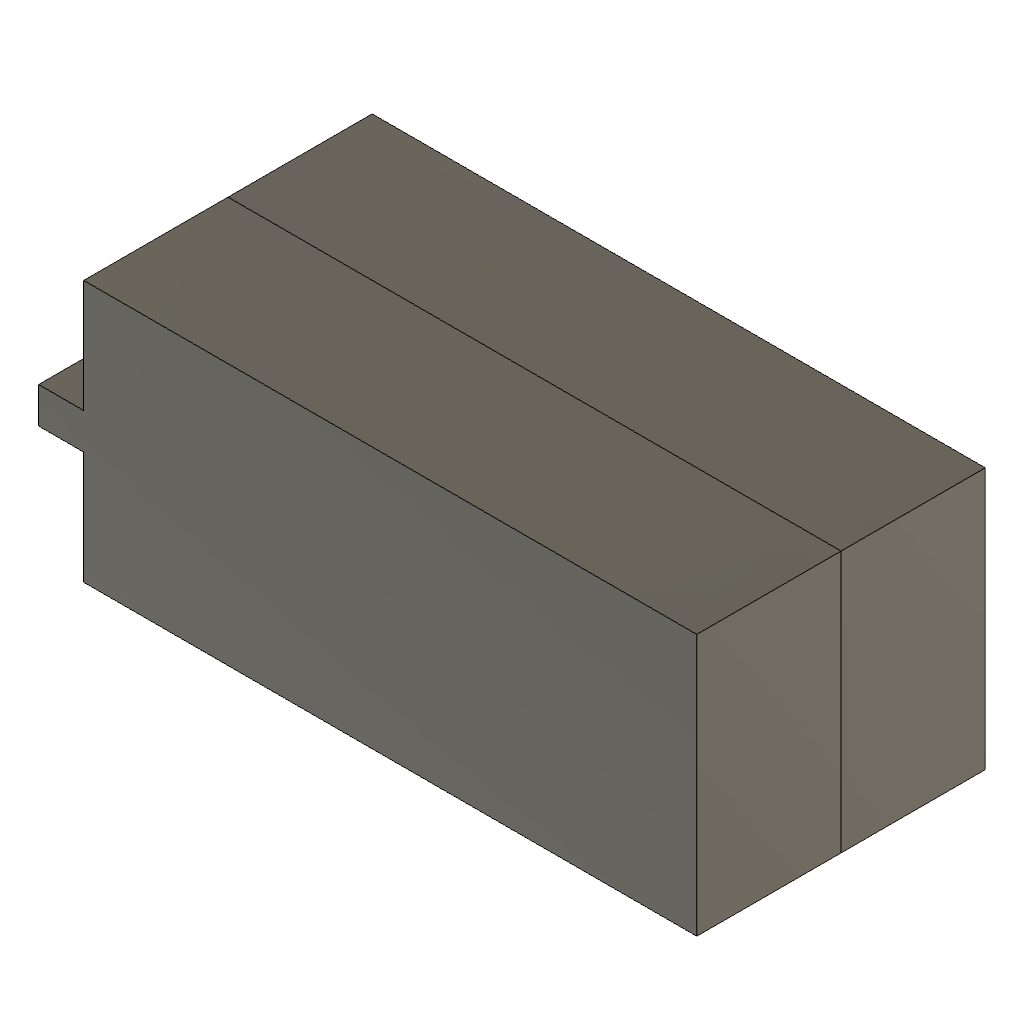
finger_mould_v1 (Autodesk Fusion 360 design; units mm, degrees)
part number: 2026-10-19-20-18-20-436
Autodesk Fusion 360 part; units mm, degrees
sketch "Esquisse2" plane through (0, 0, 0) normal (1, 0, 0) x (0, 1, 0)
  ellipse E0 centre (0, 0) end of major axis (8, 0) minor radius 6.5
  line L0 (-8, 0) -> (8, 0) construction
  line L1 (0, -6.5) -> (0, 6.5) construction
  dimension "d7" = 16
  dimension "d8" = 13
  constraint coincident E0 L0.start
  constraint coincident E0 L0.end
  constraint coincident E0 L1.start
  constraint coincident E0 L1.end
  constraint coincident E0.centre origin
  constraint horizontal L0
  measures "d7" distance of E0
extrude "Extrusion1" add sketch "Esquisse2" along normal blind 60 makes body 1
fillet "Congé1" radius 5 1 faces at (60, -0.0579, -2.16) on bodies 1
sketch "Esquisse3" plane through (0, 0, 0) normal (-1, 0, 0) x (0, -1, 0)
  ellipse E0 centre (0, 0) end of major axis (-8, 0) minor radius 6.5
  circle A0 centre (0, 0) radius 1
  dimension "d15" = 2
  constraint coincident E0.centre A0.centre
  measures "d15" diameter of A0
extrude "Extrusion2" cut sketch "Esquisse3" against normal blind 52 contours A0 bodies 1
sketch "Esquisse4" plane through (0, 0, 0) normal (1, 0, 0) x (0, 1, 0)
  line L0 (16, -14.5) -> (-16, -14.5)
  line L1 (-16, -14.5) -> (-16, 14.5)
  line L2 (-16, 14.5) -> (16, 14.5)
  line L3 (16, 14.5) -> (16, -14.5)
  line L4 (16, -14.5) -> (-16, 14.5) construction
  line L5 (-16, -14.5) -> (16, 14.5) construction
  dimension "d19" = 32
  dimension "d20" = 29
  constraint horizontal L0
  constraint perpendicular L0 L1
  constraint parallel L0 L2
  constraint parallel L1 L3
  constraint coincident L4 origin
  constraint coincident L5 origin
  measures "d19" distance of L1.end L2.end
  measures "d20" distance of L0.end L1.end
extrude "Extrusion3" add sketch "Esquisse4" along normal blind 68 separate body makes body 2
extrude "Extrusion4" add sketch "Esquisse3" along normal blind 15 and the other way blind 52 separate body contours A0 makes body 3
combine "Combiner1" operation cut target body 2 tool bodies 1 3 keep tools
split "Scinder1" by plane through (0, 0, 0) normal (0, 1, 0) bodies 2 makes body 4 at (22.6667, 16, 4.8333)
sketch "Esquisse5" plane through (0, 0, 0) normal (0, 1, 0) x (1, 0, 0)
  circle A0 centre (10, -10.5) radius 1.5
  circle A1 centre (10, 10.5) radius 1.5
  circle A2 centre (50, -10.5) radius 1.5
  circle A3 centre (50, 10.5) radius 1.5
  line L0 (0, 14.5) -> (0, -14.5)
  line L1 (0, -14.5) -> (68, -14.5)
  line L2 (0, 14.5) -> (68, 14.5)
  dimension "d31" = 3
  dimension "d32" = 3
  dimension "d33" = 3
  dimension "d34" = 3
  dimension "d35" = 10
  dimension "d36" = 10
  dimension "d37" = 50
  dimension "d38" = 50
  dimension "d39" = 4
  dimension "d40" = 4
  dimension "d41" = 4
  dimension "d42" = 4
  measures "d31" diameter of A0
  measures "d32" diameter of A1
  measures "d33" diameter of A2
  measures "d34" diameter of A3
  measures "d35" distance of A0.centre L0
  measures "d36" distance of A1.centre L0
  measures "d37" distance of A2.centre L0
  measures "d38" distance of A3.centre L0
  measures "d39" distance of A0.centre L1
  measures "d40" distance of A2.centre L1
  measures "d41" distance of A1.centre L2
  measures "d42" distance of A3.centre L2
extrude "Extrusion5" add sketch "Esquisse5" along normal blind 3 bodies 2
sketch "Esquisse6" plane through (0, 0, 0) normal (0, -1, 0) x (1, 0, 0)
  line L0 (60, 1.5) -> (60, -1.5)
  spline S0 degree 3 poles (55, -6.5) (55.3357, -6.5) (55.6706, -6.4662) (56.3285, -6.3319) (56.6499, -6.2319) (57.5578, -5.8453) (58.1013, -5.4756) (59.016, -4.5489) (59.3785, -4.0006) (59.8728, -2.7959) (60, -2.1511) (60, -1.5) knots -0.787407 -0.787407 -0.787407 -0.787407 -0.686687 -0.686687 -0.585967 -0.585967 -0.390644 -0.390644 -0.195322 -0.195322 0 0 0 0
  line L1 (55, -6.5) -> (0, -6.5)
  line L2 (0, -6.5) -> (0, -14.5)
  line L3 (0, -14.5) -> (68, -14.5)
  line L4 (68, -14.5) -> (68, 14.5)
  line L5 (68, 14.5) -> (0, 14.5)
  line L6 (0, 14.5) -> (0, 6.5)
  line L7 (0, 6.5) -> (55, 6.5)
  spline S1 degree 3 poles (60, 1.5) (60, 1.8357) (59.9662, 2.1706) (59.8319, 2.8285) (59.7319, 3.1499) (59.3453, 4.0578) (58.9756, 4.6013) (58.0489, 5.516) (57.5006, 5.8785) (56.2959, 6.3728) (55.6511, 6.5) (55, 6.5) knots -0.787407 -0.787407 -0.787407 -0.787407 -0.686687 -0.686687 -0.585967 -0.585967 -0.390644 -0.390644 -0.195322 -0.195322 0 0 0 0
  circle A0 centre (10, 10.5) radius 1.7
  circle A1 centre (10, -10.5) radius 1.7
  circle A2 centre (50, 10.5) radius 1.7
  circle A3 centre (50, -10.5) radius 1.7
  dimension "d45" = 3.4
  dimension "d46" = 3.4
  dimension "d47" = 3.4
  dimension "d48" = 3.4
  dimension "d49" = 10
  dimension "d50" = 10
  dimension "d51" = 50
  dimension "d52" = 50
  dimension "d53" = 4
  dimension "d54" = 4
  dimension "d55" = 4
  dimension "d56" = 4
  measures "d45" diameter of A0
  measures "d46" diameter of A2
  measures "d47" diameter of A3
  measures "d48" diameter of A1
  measures "d49" distance of L6 A0.centre
  measures "d50" distance of L2 A1.centre
  measures "d51" distance of L6 A2.centre
  measures "d52" distance of L2 A3.centre
  measures "d53" distance of L5 A0.centre
  measures "d54" distance of L3 A1.centre
  measures "d55" distance of L3 A3.centre
  measures "d56" distance of L5 A2.centre
extrude "Extrusion6" cut sketch "Esquisse6" against normal blind 3.5 contours A0 | A1 | A2 | A3 bodies 4
sketch "Esquisse7" plane through (0, 0, 0) normal (1, 0, 0) x (0, 1, 0)
  line L0 (16, -2) -> (-16, -2)
  line L1 (-16, -2) -> (-16, 2)
  line L2 (-16, 2) -> (16, 2)
  line L3 (16, 2) -> (16, -2)
  line L4 (16, -2) -> (-16, 2) construction
  line L5 (-16, -2) -> (16, 2) construction
  line L6 (0, 2) -> (0, -2)
  circle A0 centre (0, 0) radius 1
  dimension "d61" = 32
  dimension "d62" = 4
  dimension "d63" = 2
  constraint horizontal L0
  constraint perpendicular L0 L1
  constraint parallel L0 L2
  constraint parallel L1 L3
  constraint coincident L4 A0.centre
  constraint coincident L5 A0.centre
  constraint coincident A0.centre origin
  constraint midpoint L2 L6.start
  constraint midpoint L0 L6.end
  measures "d61" distance of L1.end L2.end
  measures "d62" distance of L0.start L2.end
  measures "d63" diameter of A0
extrude "Extrusion7" add sketch "Esquisse7" against normal blind 5 separate body contours L0 L1 L2 L6 A0 makes body 5
extrude "Extrusion8" add sketch "Esquisse7" against normal blind 5 separate body contours L0 L2 L3 L6 A0 makes body 6
combine "Combiner2" operation add target body 2 tool bodies 5
combine "Combiner3" operation add target body 4 tool bodies 6
hidden bodies 1 3
equation "doigt_largeur = 16 mm" comment "largeur du doigt au niveau de l'ongle"
equation "doigt_epaisseur = 13 mm" comment "épaisseur ongle → pulpe"
equation "doigt_longueur = 60 mm" comment "longueur totale (la pince couvre ~25-30 mm)"
equation "vaisseau_diam = 2 mm" comment "diamètre du canal pour le liquide"
equation "vaisseau_decalage = 0 mm" comment "décalage du canal par rapport au centre"
equation "d7 = doigt_largeur"
equation "d8 = doigt_epaisseur"
equation "d9 = doigt_longueur"
equation "bout_rayon = 5 mm"
equation "d13 = bout_rayon"
equation "vaisseau_fond = 8 mm"
equation "d15 = vaisseau_diam"
equation "d16 = -doigt_longueur + vaisseau_fond"
equation "paroi_moule = 8 mm"
equation "d19 = doigt_largeur + 2 * paroi_moule"
equation "d20 = doigt_epaisseur + 2 * paroi_moule"
equation "d21 = doigt_longueur + paroi_moule"
equation "tige_depasse = 15 mm"
equation "d24 = tige_depasse"
equation "d26 = doigt_longueur - vaisseau_fond"
equation "pion_diam = 3 mm"
equation "pion_haut = 3 mm"
equation "pion_jeu = 0.2 mm"
equation "d31 = pion_diam"
equation "d32 = pion_diam"
equation "d33 = pion_diam"
equation "d34 = pion_diam"
equation "d37 = doigt_longueur - 10 mm"
equation "d38 = doigt_longueur - 10 mm"
equation "d39 = paroi_moule / 2"
equation "d40 = paroi_moule / 2"
equation "d41 = paroi_moule / 2"
equation "d42 = paroi_moule / 2"
equation "d43 = pion_haut"
equation "d45 = pion_diam + 2 * pion_jeu"
equation "d46 = pion_diam + 2 * pion_jeu"
equation "d47 = pion_diam + 2 * pion_jeu"
equation "d48 = pion_diam + 2 * pion_jeu"
equation "d51 = doigt_longueur - 10 mm"
equation "d52 = doigt_longueur - 10 mm"
equation "d53 = paroi_moule / 2"
equation "d54 = paroi_moule / 2"
equation "d55 = paroi_moule / 2"
equation "d56 = paroi_moule / 2"
equation "d57 = -pion_haut - 0.5 mm"
equation "pont_epaisseur = 4 mm"
equation "pont_haut = 5 mm"
equation "d61 = doigt_largeur + 2 * paroi_moule"
equation "d62 = pont_epaisseur"
equation "d63 = vaisseau_diam"
equation "d64 = -pont_haut"
equation "d66 = -pont_haut"
named bodies: "doigt", "moule_droite", "tige", "moule_gauche", "pont_droit", "pont_gauche"
